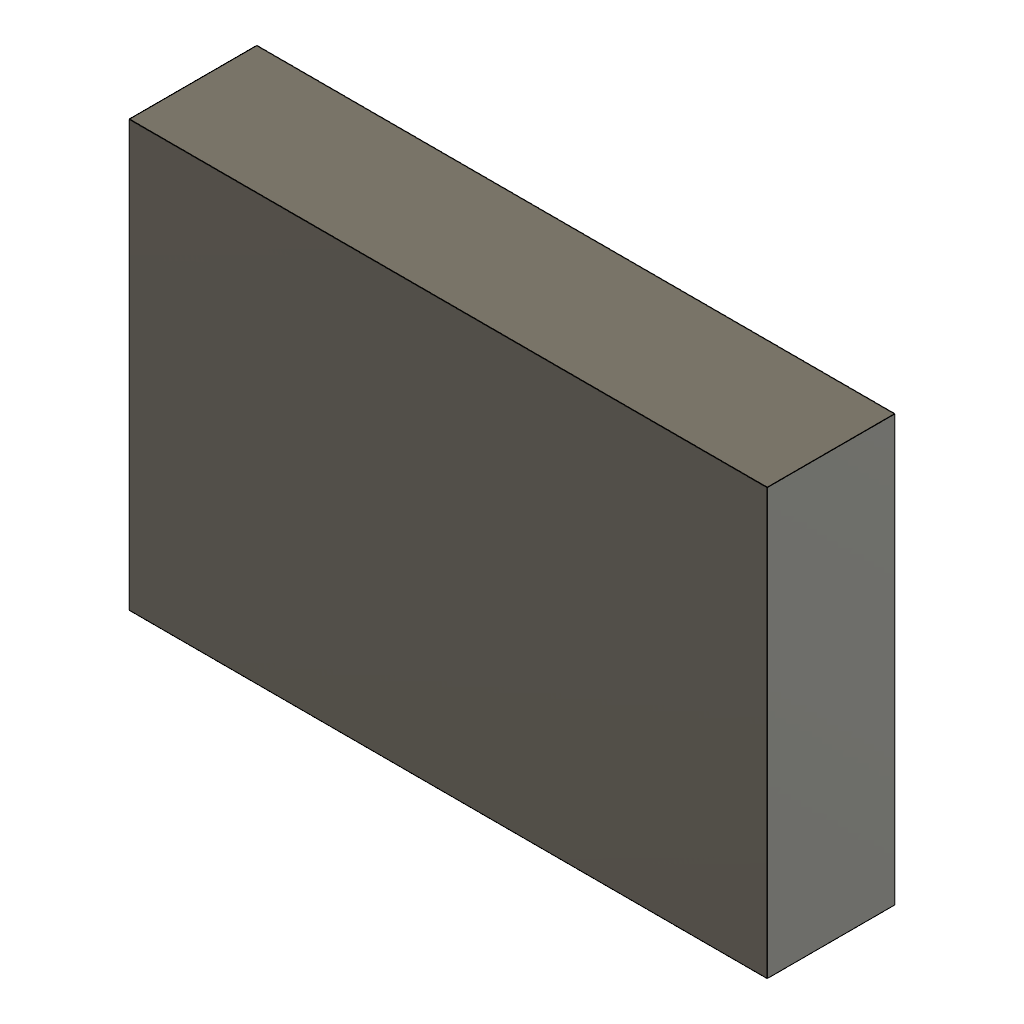
sk_on_side_face_cut (Autodesk Fusion 360 design; units mm, degrees)
part number: 2026-11-13-14-44-59-472
Autodesk Fusion 360 part; units mm, degrees
sketch "Sketch1" plane through (0, 0, 0) normal (0, 0, 1) x (1, 0, 0)
  line L0 (0, 0) -> (30, 0)
  line L1 (30, 0) -> (30, 20)
  line L2 (30, 20) -> (0, 20)
  line L3 (0, 20) -> (0, 0)
extrude "Extrude1" add sketch "Sketch1" along normal blind 6
sketch "Sketch2" plane through (0, 0, 0) normal (0, -1, 0) x (1, 0, 0)
  line L0 (0, 0) -> (30, 0)
  line L1 (30, 0) -> (30, 6)
  line L2 (30, 6) -> (0, 6)
  line L3 (0, 6) -> (0, 0)
  circle A0 centre (0, 0) radius 3
extrude "Extrude2" cut sketch "Sketch2" against normal blind 8 contours L0 L3 A0 picked at (0.9561, 1.7509)
